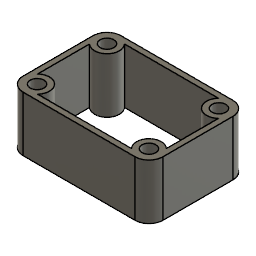
ToF_spacer_side (Autodesk Fusion 360 design; units mm, degrees)
part number: 2026-07-28-10-51-30-178
Autodesk Fusion 360 part; units mm, degrees
sketch "Sketch1" plane through (0, 0, 0) normal (0, 1, 0) x (1, 0, 0)
  line L0 (-10.16, -8.89) -> (10.16, -8.89)
  line L1 (-12.7, 6.35) -> (-12.7, -6.35)
  circle A0 centre (-10.16, 6.35) radius 1.25
  line L2 (10.16, 8.89) -> (-10.16, 8.89)
  circle A1 centre (10.16, 6.35) radius 1.25
  arc A2 (-10.16, 8.89) -> (-12.7, 6.35) centre (-10.16, 6.35) ccw
  arc A3 (10.16, -8.89) -> (12.7, -6.35) centre (10.16, -6.35) ccw
  arc A4 (12.7, 6.35) -> (10.16, 8.89) centre (10.16, 6.35) ccw
  line L3 (12.7, -6.35) -> (12.7, 6.35)
  circle A5 centre (-10.16, -6.35) radius 1.25
  circle A6 centre (10.16, -6.35) radius 1.25
  arc A7 (-12.7, -6.35) -> (-10.16, -8.89) centre (-10.16, -6.35) ccw
  line L4 (10.16, 8.89) -> (-10.16, 8.89)
  dimension "d1" = 0
  measures "d1" distance of L2
extrude "Extrude1" add sketch "Sketch1" along normal blind 10 thin wall 1 inside
